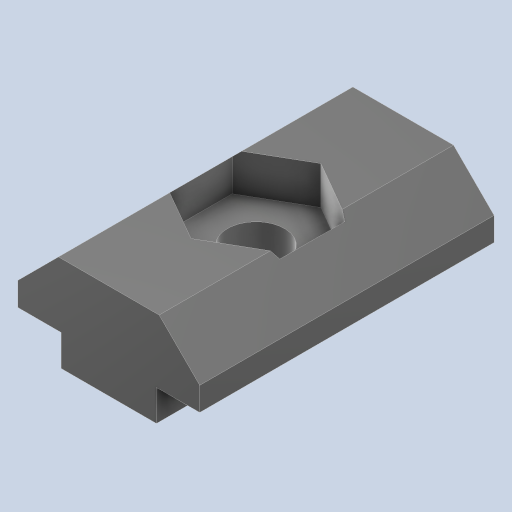
# Autodesk Inventor part: Porca perfil de alumínio
Saved by Autodesk Inventor 2026.1 (Build 301233020, 233B)
## iProperties
Created: 2025-01-14
Part Number: Porca perfil de alumínio
Material: ABS plástico
Document SubType Name: Modeling
Designer: Cliente
Density: 1.20795 g/cm^3
Appearance: Suave - Branco
Mass: 0.75 g
Surface Area: 6.41735 cm^2
Volume: 0.620888 cm^3
Author: Cliente
Autodesk Inventor part; units mm, degrees
ref_plane "YZ Plane" through (0, 0, 0) normal (1, 0, 0) x (0, 1, 0)
ref_plane "XZ Plane" through (0, 0, 0) normal (0, 1, 0) x (-1, 0, 0)
ref_plane "XY Plane" through (0, 0, 0) normal (0, 0, 1) x (1, 0, 0)
sketch "Esboço1" plane through (0, 0, 0) normal (0, 0, 1) x (1, 0, 0)
  line L0 (5.5, -2.1) -> (-5.5, -2.1)
  line L1 (-5.5, -2.1) -> (-5.5, -0.39)
  line L2 (-3.01, 2.1) -> (3.01, 2.1)
  line L3 (5.5, -0.39) -> (5.5, -2.1)
  line L4 (5.5, -2.1) -> (-5.5, 2.1) construction
  line L5 (-5.5, -2.1) -> (5.5, 2.1) construction
  line L6 (-3.01, 2.1) -> (-5.5, -0.39)
  line L7 (3.01, 2.1) -> (5.5, -0.39)
  line L8 (-3, -2.1) -> (3, -2.1)
  line L9 (-3, -2.1) -> (-3, -3.9)
  line L10 (-3, -3.9) -> (3, -3.9)
  line L11 (3, -3.9) -> (3, -2.1)
  point P0 (0, 0)
  point P1 (0, -2.1)
  dimension "d0" = 11
  dimension "d1" = 4.2
  dimension "d2" = 2.49
  dimension "d3" = 2.49
  dimension "d4" = 2.49
  dimension "d5" = 2.49
  dimension "d6" = 6
  dimension "d7" = 1.8
  constraints: 24 end point, 4 midpoint, 4 point on line, 3 perpendicular, 2 horizontal, 2 parallel, 1 vertical
  measures "d0" distance of L4.end L5.end
  measures "d1" distance of L0.end L4.end
  measures "d2" distance of L2.start L4.end
  measures "d3" distance of L1.end L4.end
  measures "d4" distance of L2.end L5.end
  measures "d5" distance of L3.start L5.end
  measures "d6" distance of L8.start L8.end
  measures "d7" distance of L8.start L9.end
extrude "Extrusão1" add sketch "Esboço1" along normal mid plane 17
sketch "Esboço2" plane through (-3.01, 2.1, -8.5) normal (0, 1, 0) x (1, 0, 0)
  line L0 (0, 0) -> (0, -17) projected
  line L1 (6.02, -17) -> (0, -17) projected
  line L2 (6.02, 0) -> (6.02, -17) projected
  line L3 (0, 0) -> (6.02, 0) projected
  line L4 (3.01, -4.7472) -> (6.26, -6.6236)
  line L5 (6.26, -6.6236) -> (6.26, -10.3764)
  line L6 (6.26, -10.3764) -> (3.01, -12.2528)
  line L7 (3.01, -12.2528) -> (-0.24, -10.3764)
  line L8 (-0.24, -10.3764) -> (-0.24, -6.6236)
  line L9 (-0.24, -6.6236) -> (3.01, -4.7472)
  point P0 (3.01, -8.5)
  point P1 (0, -8.5)
  point P2 (3.01, 0)
  dimension "d21" = 6.5
  constraints: 12 end point, 2 midpoint, 2 vertical alignment, 1 horizontal alignment, 13 other
  measures "d21" distance between parallel lines of L8 L5
extrude "Extrusão2" cut sketch "Esboço2" against normal blind 2.45 contours L9 L4 L2 L6 L7 L0 | L0 L7 L8 L9 | L4 L5 L6 L2
sketch "Esboço3" plane through (0, 0, 8.5) normal (0, 0, 1) x (1, 0, 0)
  line L0 (5.5, -0.39) -> (3.01, 2.1) projected
  line L1 (3.01, 2.1) -> (-3.01, 2.1) projected
  line L2 (-3.01, 2.1) -> (-5.5, -0.39) projected
  line L3 (-5.5, -0.39) -> (-5.5, -2.1) projected
  line L4 (-5.5, -2.1) -> (-3, -2.1) projected
  line L5 (-3, -2.1) -> (-3, -3.9) projected
  line L6 (-3, -3.9) -> (3, -3.9) projected
  line L7 (3, -3.9) -> (3, -2.1) projected
  line L8 (3, -2.1) -> (5.5, -2.1) projected
  line L9 (5.5, -2.1) -> (5.5, -0.39) projected
  line L10 (-2.9064, 1.85) -> (2.9064, 1.85)
  line L11 (2.9064, 1.85) -> (5.25, -0.4936)
  line L12 (5.25, -0.4936) -> (5.25, -1.85)
  line L13 (5.25, -1.85) -> (2.75, -1.85)
  line L14 (2.75, -1.85) -> (2.75, -3.65)
  line L15 (2.75, -3.65) -> (-2.75, -3.65)
  line L16 (-2.75, -3.65) -> (-2.75, -1.85)
  line L17 (-2.75, -1.85) -> (-5.25, -1.85)
  line L18 (-5.25, -1.85) -> (-5.25, -0.4936)
  line L19 (-5.25, -0.4936) -> (-2.9064, 1.85)
  line L20 (-2.75, -3.65) -> (-2.75, -3.9)
  line L21 (2.75, -3.65) -> (2.75, -3.9)
  point P0 (0, 0)
  dimension "d13" = 0.25
  constraints: 24 end point, 2 point on line, 1 parallel, 1 perpendicular, 9 other
  measures "d13" distance between parallel lines of L1 L10
extrude "Extrusão3" cut sketch "Esboço3" against normal through all contours L9 L8 L7 L6 L21 L14 L13 L12 L11 L10 L19 L18 L17 L16 L20 L5 L4 L3 L2 L1 L0 | L6 L20 L15 L21
sketch "Esboço4" plane through (-3.01, -0.35, -8.5) normal (0, 1, 0) x (1, 0, 0)
  line L0 (5.76, 0) -> (0.26, 0) projected
  line L1 (5.76, -17) -> (5.76, 0) projected
  line L2 (0.26, -17) -> (5.76, -17) projected
  line L3 (0.26, -17) -> (0.26, 0) projected
  circle A0 centre (3.01, -8.5) radius 1.65
  point P0 (0.26, -8.5)
  point P1 (3.01, 0)
  dimension "d22" = 3.3
  constraints: 2 midpoint, 1 centre point, 1 horizontal alignment, 1 vertical alignment
  measures "d22" diameter of A0
extrude "Extrusão4" cut sketch "Esboço4" against normal through all contours A0
chamfer "Chanfro1" distance 1 angle 45 1 edges at (-1.65, -3.65, 0)
equation "\"d3\" = d2"
equation "\"d4\" = d2"
equation "\"d5\" = d4"
